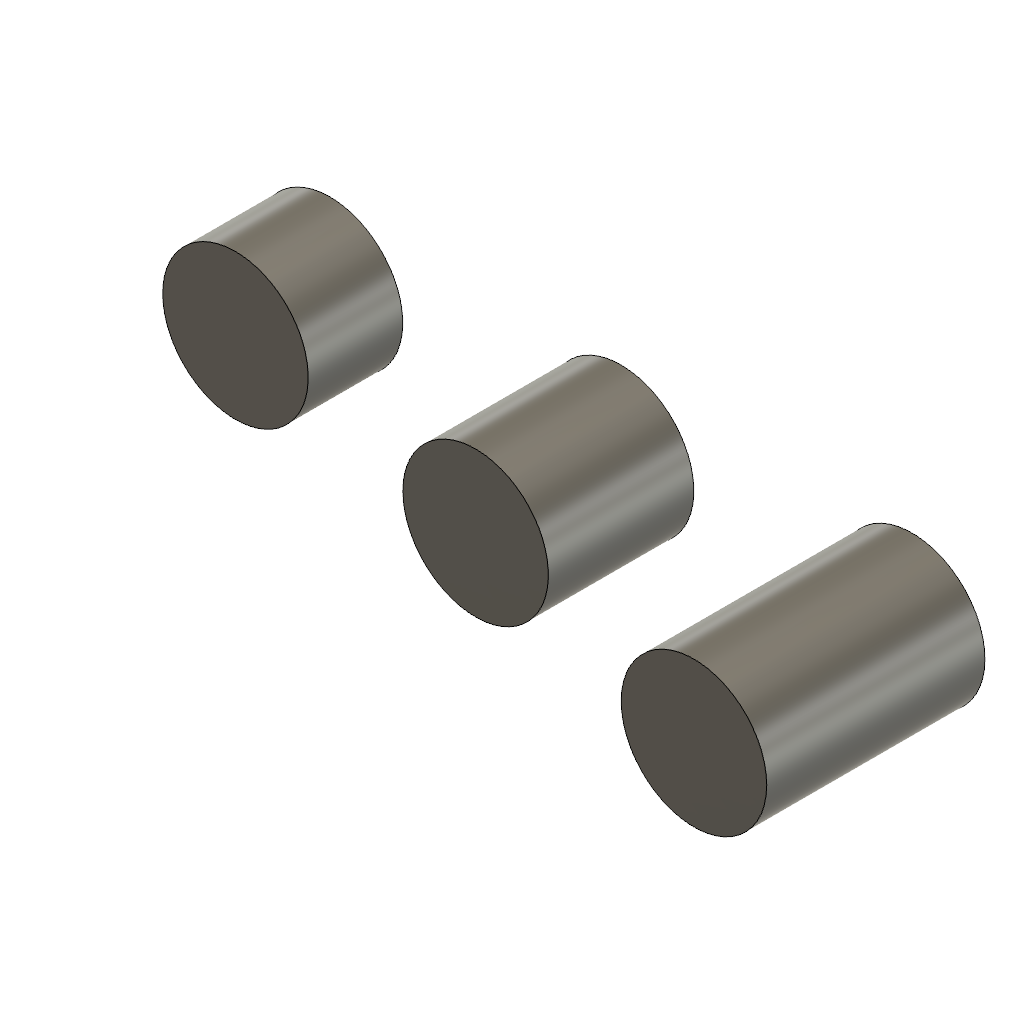
vendor_ControlEdited (Autodesk Fusion 360 design; units mm, degrees)
part number: 2026-10-20-18-44-58-122
Autodesk Fusion 360 part; units mm, degrees
sketch "ProfileA" plane through (0, 0, 0) normal (0, 0, 1) x (1, 0, 0)
  circle A0 centre (0, 0) radius 10
extrude "ExtrusionA" add sketch "ProfileA" along normal blind 13 makes body 1
sketch "ProfileB" plane through (0, 0, 0) normal (0, 0, 1) x (1, 0, 0)
  circle A0 centre (40, 0) radius 10
sketch "ProfileC" plane through (0, 0, 0) normal (0, 0, 1) x (1, 0, 0)
  circle A0 centre (80, 0) radius 10
extrude "ExtrusionB" add sketch "ProfileB" along normal blind 20 separate body makes body 2
extrude "ExtrusionC" add sketch "ProfileC" along normal blind 30 separate body makes body 3
